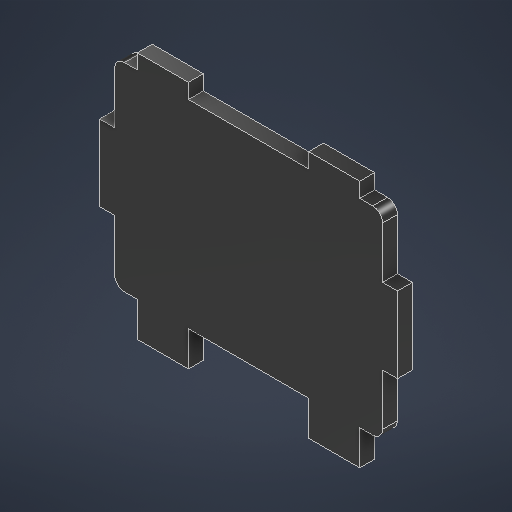
# Autodesk Inventor part: TransmitterFace
Saved by Autodesk Inventor 2027.1 (Build 311270010, 270A)
## iProperties
Created: 2026-10-16
Part Number: TransmitterFace
Material: MDF Medium Density Fiberboard
Document SubType Name: Modeling
Designer: SDS Scholar
Density: 0.8 g/cm^3
Appearance: Glossy - Black
Mass: 6.4603 g
Surface Area: 61.1383 cm^2
Volume: 8.07537 cm^3
Author: SDS Scholar
Autodesk Inventor part; units mm, degrees
ref_plane "YZ Plane" through (0, 0, 0) normal (1, 0, 0) x (0, 1, 0)
ref_plane "XZ Plane" through (0, 0, 0) normal (0, 1, 0) x (-1, 0, 0)
ref_plane "XY Plane" through (0, 0, 0) normal (0, 0, 1) x (1, 0, 0)
sketch "Sketch1" plane through (0, 0, 0) normal (0, 0, 1) x (1, 0, 0)
  line L0 (27, 20) -> (-27, 20)
  line L1 (-27, 20) -> (-27, -20)
  line L2 (-27, -20) -> (27, -20)
  line L3 (27, -20) -> (27, 20)
  line L4 (22.4, 20) -> (12.1, 20)
  line L5 (12.1, 20) -> (12.1, 23)
  line L6 (12.1, 23) -> (22.4, 23)
  line L7 (22.4, 23) -> (22.4, 20)
  line L8 (27, 20) -> (4.5, 20) construction
  line L9 (0, 20) -> (0, -20) construction
  line L10 (22.4, -20) -> (12.1, -20)
  line L11 (12.1, -20) -> (12.1, -27)
  line L12 (12.1, -27) -> (22.4, -27)
  line L13 (22.4, -27) -> (22.4, -20)
  line L14 (27, 7.65) -> (30, 7.65)
  line L15 (30, 7.65) -> (30, -7.65)
  line L16 (30, -7.65) -> (27, -7.65)
  line L17 (27, -7.65) -> (27, 7.65)
  line L18 (-12.1, 20) -> (-12.1, 23)
  line L19 (-12.1, 23) -> (-22.4, 23)
  line L20 (-22.4, 23) -> (-22.4, 20)
  line L21 (-12.1, -20) -> (-12.1, -27)
  line L22 (-12.1, -27) -> (-22.4, -27)
  line L23 (-22.4, -27) -> (-22.4, -20)
  line L24 (-27, 7.65) -> (-30, 7.65)
  line L25 (-30, 7.65) -> (-30, -7.65)
  line L26 (-30, -7.65) -> (-27, -7.65)
  point P0 (0, 0)
  point P1 (-27, 0)
  point P2 (30, 0)
  point P3 (0, 0)
  point P4 (12.1, -20)
  point P5 (27, -7.65)
  point P6 (-12.1, 20)
  point P7 (-22.4, 20)
  point P8 (-27, 7.65)
  point P9 (-27, -7.65)
  point P10 (-22.4, -20)
  point P11 (-12.1, -20)
  point P12 (-30, 0)
  point P13 (17.25, 23)
  point P14 (-17.25, -27)
  point P15 (17.25, -27)
  point P16 (-17.25, 23)
  dimension "d39" = 40
  dimension "d40" = 54
  dimension "d47" = 3
  dimension "d48" = 10.3
  dimension "d49" = 10.3
  dimension "d50" = 7
  dimension "d51" = 15.3
  dimension "d52" = 3
  dimension "d57" = 34.5
  dimension "d58" = 34.5
  constraints: 54 end point, 12 symmetric about line, 10 midpoint, 8 parallel, 4 horizontal, 4 perpendicular, 4 point on line, 3 horizontal alignment, 2 vertical alignment
  measures "d39" distance of L0.end L1.end
  measures "d40" distance of L1.end L2.end
  measures "d47" distance of L6.end L4.start
  measures "d48" distance of L5.end L6.end
  measures "d49" distance of L11.end L12.end
  measures "d50" distance of L12.end L10.start
  measures "d51" distance of L14.end L15.end
  measures "d52" distance of L15.end L16.end
  measures "d57" distance of point (-17.25, -27) point (17.25, -27)
  measures "d58" distance of point (-17.25, 23) point (17.25, 23)
extrude "Extrusion1" add sketch "Sketch1" along normal blind 3
fillet "Fillet3" [suppressed]
fillet "Fillet4" radius 2 4 edges at (-27, 20, 1.5) (27, 20, 1.5) (27, -20, 1.5) (-27, -20, 1.5)
body "Solid1"
